Autodesk Fusion 360 part; units mm, degrees
(part 2 of 5)
sketch "roof_pa14" plane through (132.4571, 0, 0) normal (1, 0, 0) x (0, 0, -1)
  line L0 (-14.9035, -20.1869) -> (-16.1761, -17.303)
  line L1 (-16.1761, -17.303) -> (-17.2529, -14.4192)
  line L2 (-17.2529, -14.4192) -> (-18.1339, -11.5353)
  line L3 (-18.1339, -11.5353) -> (-18.8192, -8.6515)
  line L4 (-18.8192, -8.6515) -> (-19.3086, -5.7677)
  line L5 (-19.3086, -5.7677) -> (-19.6023, -2.8838)
  line L6 (-19.6023, -2.8838) -> (-19.7002, 0)
  line L7 (-19.7002, 0) -> (-19.6023, 2.8838)
  line L8 (-19.6023, 2.8838) -> (-19.3086, 5.7677)
  line L9 (-19.3086, 5.7677) -> (-18.8192, 8.6515)
  line L10 (-18.8192, 8.6515) -> (-18.1339, 11.5353)
  line L11 (-18.1339, 11.5353) -> (-17.2529, 14.4192)
  line L12 (-17.2529, 14.4192) -> (-16.1761, 17.303)
  line L13 (-16.1761, 17.303) -> (-14.9035, 20.1869)
  line L14 (-14.9035, 20.1869) -> (-12.9035, 20.1869)
  line L15 (-12.9035, 20.1869) -> (-14.1761, 17.303)
  line L16 (-14.1761, 17.303) -> (-15.2529, 14.4192)
  line L17 (-15.2529, 14.4192) -> (-16.1339, 11.5353)
  line L18 (-16.1339, 11.5353) -> (-16.8192, 8.6515)
  line L19 (-16.8192, 8.6515) -> (-17.3086, 5.7677)
  line L20 (-17.3086, 5.7677) -> (-17.6023, 2.8838)
  line L21 (-17.6023, 2.8838) -> (-17.7002, 0)
  line L22 (-17.7002, 0) -> (-17.6023, -2.8838)
  line L23 (-17.6023, -2.8838) -> (-17.3086, -5.7677)
  line L24 (-17.3086, -5.7677) -> (-16.8192, -8.6515)
  line L25 (-16.8192, -8.6515) -> (-16.1339, -11.5353)
  line L26 (-16.1339, -11.5353) -> (-15.2529, -14.4192)
  line L27 (-15.2529, -14.4192) -> (-14.1761, -17.303)
  line L28 (-14.1761, -17.303) -> (-12.9035, -20.1869)
  line L29 (-12.9035, -20.1869) -> (-14.9035, -20.1869)
ref_plane "WorkPlane30" through (137.5429, 0, 0) normal (1, 0, 0) x (0, 1, 0)
sketch "roof_pb14" plane through (137.5429, 0, 0) normal (1, 0, 0) x (0, 0, -1)
  line L0 (-13.3531, -18.2995) -> (-14.5006, -15.6853)
  line L1 (-14.5006, -15.6853) -> (-15.4714, -13.0711)
  line L2 (-15.4714, -13.0711) -> (-16.2658, -10.4568)
  line L3 (-16.2658, -10.4568) -> (-16.8836, -7.8426)
  line L4 (-16.8836, -7.8426) -> (-17.325, -5.2284)
  line L5 (-17.325, -5.2284) -> (-17.5897, -2.6142)
  line L6 (-17.5897, -2.6142) -> (-17.678, 0)
  line L7 (-17.678, 0) -> (-17.5897, 2.6142)
  line L8 (-17.5897, 2.6142) -> (-17.325, 5.2284)
  line L9 (-17.325, 5.2284) -> (-16.8836, 7.8426)
  line L10 (-16.8836, 7.8426) -> (-16.2658, 10.4568)
  line L11 (-16.2658, 10.4568) -> (-15.4714, 13.0711)
  line L12 (-15.4714, 13.0711) -> (-14.5006, 15.6853)
  line L13 (-14.5006, 15.6853) -> (-13.3531, 18.2995)
  line L14 (-13.3531, 18.2995) -> (-11.3531, 18.2995)
  line L15 (-11.3531, 18.2995) -> (-12.5006, 15.6853)
  line L16 (-12.5006, 15.6853) -> (-13.4714, 13.0711)
  line L17 (-13.4714, 13.0711) -> (-14.2658, 10.4568)
  line L18 (-14.2658, 10.4568) -> (-14.8836, 7.8426)
  line L19 (-14.8836, 7.8426) -> (-15.325, 5.2284)
  line L20 (-15.325, 5.2284) -> (-15.5897, 2.6142)
  line L21 (-15.5897, 2.6142) -> (-15.678, 0)
  line L22 (-15.678, 0) -> (-15.5897, -2.6142)
  line L23 (-15.5897, -2.6142) -> (-15.325, -5.2284)
  line L24 (-15.325, -5.2284) -> (-14.8836, -7.8426)
  line L25 (-14.8836, -7.8426) -> (-14.2658, -10.4568)
  line L26 (-14.2658, -10.4568) -> (-13.4714, -13.0711)
  line L27 (-13.4714, -13.0711) -> (-12.5006, -15.6853)
  line L28 (-12.5006, -15.6853) -> (-11.3531, -18.2995)
  line L29 (-11.3531, -18.2995) -> (-13.3531, -18.2995)
loft "Loft15" add profiles "roof_pa14", "roof_pb14" section 1 section 2 separate body makes body 15
ref_plane "WorkPlane31" through (136.7429, 0, 0) normal (1, 0, 0) x (0, 1, 0)
sketch "roof_pa15" plane through (136.7429, 0, 0) normal (1, 0, 0) x (0, 0, -1)
  line L0 (-13.3531, -18.2995) -> (-14.5006, -15.6853)
  line L1 (-14.5006, -15.6853) -> (-15.4714, -13.0711)
  line L2 (-15.4714, -13.0711) -> (-16.2658, -10.4568)
  line L3 (-16.2658, -10.4568) -> (-16.8836, -7.8426)
  line L4 (-16.8836, -7.8426) -> (-17.325, -5.2284)
  line L5 (-17.325, -5.2284) -> (-17.5897, -2.6142)
  line L6 (-17.5897, -2.6142) -> (-17.678, 0)
  line L7 (-17.678, 0) -> (-17.5897, 2.6142)
  line L8 (-17.5897, 2.6142) -> (-17.325, 5.2284)
  line L9 (-17.325, 5.2284) -> (-16.8836, 7.8426)
  line L10 (-16.8836, 7.8426) -> (-16.2658, 10.4568)
  line L11 (-16.2658, 10.4568) -> (-15.4714, 13.0711)
  line L12 (-15.4714, 13.0711) -> (-14.5006, 15.6853)
  line L13 (-14.5006, 15.6853) -> (-13.3531, 18.2995)
  line L14 (-13.3531, 18.2995) -> (-11.3531, 18.2995)
  line L15 (-11.3531, 18.2995) -> (-12.5006, 15.6853)
  line L16 (-12.5006, 15.6853) -> (-13.4714, 13.0711)
  line L17 (-13.4714, 13.0711) -> (-14.2658, 10.4568)
  line L18 (-14.2658, 10.4568) -> (-14.8836, 7.8426)
  line L19 (-14.8836, 7.8426) -> (-15.325, 5.2284)
  line L20 (-15.325, 5.2284) -> (-15.5897, 2.6142)
  line L21 (-15.5897, 2.6142) -> (-15.678, 0)
  line L22 (-15.678, 0) -> (-15.5897, -2.6142)
  line L23 (-15.5897, -2.6142) -> (-15.325, -5.2284)
  line L24 (-15.325, -5.2284) -> (-14.8836, -7.8426)
  line L25 (-14.8836, -7.8426) -> (-14.2658, -10.4568)
  line L26 (-14.2658, -10.4568) -> (-13.4714, -13.0711)
  line L27 (-13.4714, -13.0711) -> (-12.5006, -15.6853)
  line L28 (-12.5006, -15.6853) -> (-11.3531, -18.2995)
  line L29 (-11.3531, -18.2995) -> (-13.3531, -18.2995)
ref_plane "WorkPlane32" through (141.8286, 0, 0) normal (1, 0, 0) x (0, 1, 0)
sketch "roof_pb15" plane through (141.8286, 0, 0) normal (1, 0, 0) x (0, 0, -1)
  line L0 (-11.8605, -16.4823) -> (-12.8874, -14.1277)
  line L1 (-12.8874, -14.1277) -> (-13.7563, -11.7731)
  line L2 (-13.7563, -11.7731) -> (-14.4672, -9.4185)
  line L3 (-14.4672, -9.4185) -> (-15.0202, -7.0639)
  line L4 (-15.0202, -7.0639) -> (-15.4151, -4.7092)
  line L5 (-15.4151, -4.7092) -> (-15.6521, -2.3546)
  line L6 (-15.6521, -2.3546) -> (-15.7311, 0)
  line L7 (-15.7311, 0) -> (-15.6521, 2.3546)
  line L8 (-15.6521, 2.3546) -> (-15.4151, 4.7092)
  line L9 (-15.4151, 4.7092) -> (-15.0202, 7.0639)
  line L10 (-15.0202, 7.0639) -> (-14.4672, 9.4185)
  line L11 (-14.4672, 9.4185) -> (-13.7563, 11.7731)
  line L12 (-13.7563, 11.7731) -> (-12.8874, 14.1277)
  line L13 (-12.8874, 14.1277) -> (-11.8605, 16.4823)
  line L14 (-11.8605, 16.4823) -> (-9.8605, 16.4823)
  line L15 (-9.8605, 16.4823) -> (-10.8874, 14.1277)
  line L16 (-10.8874, 14.1277) -> (-11.7563, 11.7731)
  line L17 (-11.7563, 11.7731) -> (-12.4672, 9.4185)
  line L18 (-12.4672, 9.4185) -> (-13.0202, 7.0639)
  line L19 (-13.0202, 7.0639) -> (-13.4151, 4.7092)
  line L20 (-13.4151, 4.7092) -> (-13.6521, 2.3546)
  line L21 (-13.6521, 2.3546) -> (-13.7311, 0)
  line L22 (-13.7311, 0) -> (-13.6521, -2.3546)
  line L23 (-13.6521, -2.3546) -> (-13.4151, -4.7092)
  line L24 (-13.4151, -4.7092) -> (-13.0202, -7.0639)
  line L25 (-13.0202, -7.0639) -> (-12.4672, -9.4185)
  line L26 (-12.4672, -9.4185) -> (-11.7563, -11.7731)
  line L27 (-11.7563, -11.7731) -> (-10.8874, -14.1277)
  line L28 (-10.8874, -14.1277) -> (-9.8605, -16.4823)
  line L29 (-9.8605, -16.4823) -> (-11.8605, -16.4823)
loft "Loft16" add profiles "roof_pa15", "roof_pb15" section 1 section 2 separate body makes body 16
ref_plane "WorkPlane33" through (141.0286, 0, 0) normal (1, 0, 0) x (0, 1, 0)
sketch "roof_pa16" plane through (141.0286, 0, 0) normal (1, 0, 0) x (0, 0, -1)
  line L0 (-11.8605, -16.4823) -> (-12.8874, -14.1277)
  line L1 (-12.8874, -14.1277) -> (-13.7563, -11.7731)
  line L2 (-13.7563, -11.7731) -> (-14.4672, -9.4185)
  line L3 (-14.4672, -9.4185) -> (-15.0202, -7.0639)
  line L4 (-15.0202, -7.0639) -> (-15.4151, -4.7092)
  line L5 (-15.4151, -4.7092) -> (-15.6521, -2.3546)
  line L6 (-15.6521, -2.3546) -> (-15.7311, 0)
  line L7 (-15.7311, 0) -> (-15.6521, 2.3546)
  line L8 (-15.6521, 2.3546) -> (-15.4151, 4.7092)
  line L9 (-15.4151, 4.7092) -> (-15.0202, 7.0639)
  line L10 (-15.0202, 7.0639) -> (-14.4672, 9.4185)
  line L11 (-14.4672, 9.4185) -> (-13.7563, 11.7731)
  line L12 (-13.7563, 11.7731) -> (-12.8874, 14.1277)
  line L13 (-12.8874, 14.1277) -> (-11.8605, 16.4823)
  line L14 (-11.8605, 16.4823) -> (-9.8605, 16.4823)
  line L15 (-9.8605, 16.4823) -> (-10.8874, 14.1277)
  line L16 (-10.8874, 14.1277) -> (-11.7563, 11.7731)
  line L17 (-11.7563, 11.7731) -> (-12.4672, 9.4185)
  line L18 (-12.4672, 9.4185) -> (-13.0202, 7.0639)
  line L19 (-13.0202, 7.0639) -> (-13.4151, 4.7092)
  line L20 (-13.4151, 4.7092) -> (-13.6521, 2.3546)
  line L21 (-13.6521, 2.3546) -> (-13.7311, 0)
  line L22 (-13.7311, 0) -> (-13.6521, -2.3546)
  line L23 (-13.6521, -2.3546) -> (-13.4151, -4.7092)
  line L24 (-13.4151, -4.7092) -> (-13.0202, -7.0639)
  line L25 (-13.0202, -7.0639) -> (-12.4672, -9.4185)
  line L26 (-12.4672, -9.4185) -> (-11.7563, -11.7731)
  line L27 (-11.7563, -11.7731) -> (-10.8874, -14.1277)
  line L28 (-10.8874, -14.1277) -> (-9.8605, -16.4823)
  line L29 (-9.8605, -16.4823) -> (-11.8605, -16.4823)
ref_plane "WorkPlane34" through (146.1143, 0, 0) normal (1, 0, 0) x (0, 1, 0)
sketch "roof_pb16" plane through (146.1143, 0, 0) normal (1, 0, 0) x (0, 0, -1)
  line L0 (-10.4123, -14.7193) -> (-11.3222, -12.6165)
  line L1 (-11.3222, -12.6165) -> (-12.0922, -10.5138)
  line L2 (-12.0922, -10.5138) -> (-12.7222, -8.411)
  line L3 (-12.7222, -8.411) -> (-13.2121, -6.3083)
  line L4 (-13.2121, -6.3083) -> (-13.5621, -4.2055)
  line L5 (-13.5621, -4.2055) -> (-13.7721, -2.1028)
  line L6 (-13.7721, -2.1028) -> (-13.8421, 0)
  line L7 (-13.8421, 0) -> (-13.7721, 2.1028)
  line L8 (-13.7721, 2.1028) -> (-13.5621, 4.2055)
  line L9 (-13.5621, 4.2055) -> (-13.2121, 6.3083)
  line L10 (-13.2121, 6.3083) -> (-12.7222, 8.411)
  line L11 (-12.7222, 8.411) -> (-12.0922, 10.5138)
  line L12 (-12.0922, 10.5138) -> (-11.3222, 12.6165)
  line L13 (-11.3222, 12.6165) -> (-10.4123, 14.7193)
  line L14 (-10.4123, 14.7193) -> (-8.4123, 14.7193)
  line L15 (-8.4123, 14.7193) -> (-9.3222, 12.6165)
  line L16 (-9.3222, 12.6165) -> (-10.0922, 10.5138)
  line L17 (-10.0922, 10.5138) -> (-10.7222, 8.411)
  line L18 (-10.7222, 8.411) -> (-11.2121, 6.3083)
  line L19 (-11.2121, 6.3083) -> (-11.5621, 4.2055)
  line L20 (-11.5621, 4.2055) -> (-11.7721, 2.1028)
  line L21 (-11.7721, 2.1028) -> (-11.8421, 0)
  line L22 (-11.8421, 0) -> (-11.7721, -2.1028)
  line L23 (-11.7721, -2.1028) -> (-11.5621, -4.2055)
  line L24 (-11.5621, -4.2055) -> (-11.2121, -6.3083)
  line L25 (-11.2121, -6.3083) -> (-10.7222, -8.411)
  line L26 (-10.7222, -8.411) -> (-10.0922, -10.5138)
  line L27 (-10.0922, -10.5138) -> (-9.3222, -12.6165)
  line L28 (-9.3222, -12.6165) -> (-8.4123, -14.7193)
  line L29 (-8.4123, -14.7193) -> (-10.4123, -14.7193)
loft "Loft17" add profiles "roof_pa16", "roof_pb16" section 1 section 2 separate body makes body 17
ref_plane "WorkPlane35" through (145.3143, 0, 0) normal (1, 0, 0) x (0, 1, 0)
sketch "roof_pa17" plane through (145.3143, 0, 0) normal (1, 0, 0) x (0, 0, -1)
  line L0 (-10.4123, -14.7193) -> (-11.3222, -12.6165)
  line L1 (-11.3222, -12.6165) -> (-12.0922, -10.5138)
  line L2 (-12.0922, -10.5138) -> (-12.7222, -8.411)
  line L3 (-12.7222, -8.411) -> (-13.2121, -6.3083)
  line L4 (-13.2121, -6.3083) -> (-13.5621, -4.2055)
  line L5 (-13.5621, -4.2055) -> (-13.7721, -2.1028)
  line L6 (-13.7721, -2.1028) -> (-13.8421, 0)
  line L7 (-13.8421, 0) -> (-13.7721, 2.1028)
  line L8 (-13.7721, 2.1028) -> (-13.5621, 4.2055)
  line L9 (-13.5621, 4.2055) -> (-13.2121, 6.3083)
  line L10 (-13.2121, 6.3083) -> (-12.7222, 8.411)
  line L11 (-12.7222, 8.411) -> (-12.0922, 10.5138)
  line L12 (-12.0922, 10.5138) -> (-11.3222, 12.6165)
  line L13 (-11.3222, 12.6165) -> (-10.4123, 14.7193)
  line L14 (-10.4123, 14.7193) -> (-8.4123, 14.7193)
  line L15 (-8.4123, 14.7193) -> (-9.3222, 12.6165)
  line L16 (-9.3222, 12.6165) -> (-10.0922, 10.5138)
  line L17 (-10.0922, 10.5138) -> (-10.7222, 8.411)
  line L18 (-10.7222, 8.411) -> (-11.2121, 6.3083)
  line L19 (-11.2121, 6.3083) -> (-11.5621, 4.2055)
  line L20 (-11.5621, 4.2055) -> (-11.7721, 2.1028)
  line L21 (-11.7721, 2.1028) -> (-11.8421, 0)
  line L22 (-11.8421, 0) -> (-11.7721, -2.1028)
  line L23 (-11.7721, -2.1028) -> (-11.5621, -4.2055)
  line L24 (-11.5621, -4.2055) -> (-11.2121, -6.3083)
  line L25 (-11.2121, -6.3083) -> (-10.7222, -8.411)
  line L26 (-10.7222, -8.411) -> (-10.0922, -10.5138)
  line L27 (-10.0922, -10.5138) -> (-9.3222, -12.6165)
  line L28 (-9.3222, -12.6165) -> (-8.4123, -14.7193)
  line L29 (-8.4123, -14.7193) -> (-10.4123, -14.7193)
ref_plane "WorkPlane36" through (150, 0, 0) normal (1, 0, 0) x (0, 1, 0)
sketch "roof_pb17" plane through (150, 0, 0) normal (1, 0, 0) x (0, 0, -1)
  line L0 (-9, -13) -> (-9.7959, -11.1429)
  line L1 (-9.7959, -11.1429) -> (-10.4694, -9.2857)
  line L2 (-10.4694, -9.2857) -> (-11.0204, -7.4286)
  line L3 (-11.0204, -7.4286) -> (-11.449, -5.5714)
  line L4 (-11.449, -5.5714) -> (-11.7551, -3.7143)
  line L5 (-11.7551, -3.7143) -> (-11.9388, -1.8571)
  line L6 (-11.9388, -1.8571) -> (-12, 0)
  line L7 (-12, 0) -> (-11.9388, 1.8571)
  line L8 (-11.9388, 1.8571) -> (-11.7551, 3.7143)
  line L9 (-11.7551, 3.7143) -> (-11.449, 5.5714)
  line L10 (-11.449, 5.5714) -> (-11.0204, 7.4286)
  line L11 (-11.0204, 7.4286) -> (-10.4694, 9.2857)
  line L12 (-10.4694, 9.2857) -> (-9.7959, 11.1429)
  line L13 (-9.7959, 11.1429) -> (-9, 13)
  line L14 (-9, 13) -> (-7, 13)
  line L15 (-7, 13) -> (-7.7959, 11.1429)
  line L16 (-7.7959, 11.1429) -> (-8.4694, 9.2857)
  line L17 (-8.4694, 9.2857) -> (-9.0204, 7.4286)
  line L18 (-9.0204, 7.4286) -> (-9.449, 5.5714)
  line L19 (-9.449, 5.5714) -> (-9.7551, 3.7143)
  line L20 (-9.7551, 3.7143) -> (-9.9388, 1.8571)
  line L21 (-9.9388, 1.8571) -> (-10, 0)
  line L22 (-10, 0) -> (-9.9388, -1.8571)
  line L23 (-9.9388, -1.8571) -> (-9.7551, -3.7143)
  line L24 (-9.7551, -3.7143) -> (-9.449, -5.5714)
  line L25 (-9.449, -5.5714) -> (-9.0204, -7.4286)
  line L26 (-9.0204, -7.4286) -> (-8.4694, -9.2857)
  line L27 (-8.4694, -9.2857) -> (-7.7959, -11.1429)
  line L28 (-7.7959, -11.1429) -> (-7, -13)
  line L29 (-7, -13) -> (-9, -13)
loft "Loft18" add profiles "roof_pa17", "roof_pb17" section 1 section 2 separate body makes body 18
ref_plane "WorkPlane37" through (-24, 0, 0) normal (1, 0, 0) x (0, 1, 0)
sketch "belly_pa00" plane through (-24, 0, 0) normal (1, 0, 0) x (0, 0, -1)
  line L0 (24.5, -33) -> (25.6939, -28.2857)
  line L1 (25.6939, -28.2857) -> (26.7041, -23.5714)
  line L2 (26.7041, -23.5714) -> (27.5306, -18.8571)
  line L3 (27.5306, -18.8571) -> (28.1735, -14.1429)
  line L4 (28.1735, -14.1429) -> (28.6327, -9.4286)
  line L5 (28.6327, -9.4286) -> (28.9082, -4.7143)
  line L6 (28.9082, -4.7143) -> (29, 0)
  line L7 (29, 0) -> (28.9082, 4.7143)
  line L8 (28.9082, 4.7143) -> (28.6327, 9.4286)
  line L9 (28.6327, 9.4286) -> (28.1735, 14.1429)
  line L10 (28.1735, 14.1429) -> (27.5306, 18.8571)
  line L11 (27.5306, 18.8571) -> (26.7041, 23.5714)
  line L12 (26.7041, 23.5714) -> (25.6939, 28.2857)
  line L13 (25.6939, 28.2857) -> (24.5, 33)
  line L14 (24.5, 33) -> (22.5, 33)
  line L15 (22.5, 33) -> (23.6939, 28.2857)
  line L16 (23.6939, 28.2857) -> (24.7041, 23.5714)
  line L17 (24.7041, 23.5714) -> (25.5306, 18.8571)
  line L18 (25.5306, 18.8571) -> (26.1735, 14.1429)
  line L19 (26.1735, 14.1429) -> (26.6327, 9.4286)
  line L20 (26.6327, 9.4286) -> (26.9082, 4.7143)
  line L21 (26.9082, 4.7143) -> (27, 0)
  line L22 (27, 0) -> (26.9082, -4.7143)
  line L23 (26.9082, -4.7143) -> (26.6327, -9.4286)
  line L24 (26.6327, -9.4286) -> (26.1735, -14.1429)
  line L25 (26.1735, -14.1429) -> (25.5306, -18.8571)
  line L26 (25.5306, -18.8571) -> (24.7041, -23.5714)
  line L27 (24.7041, -23.5714) -> (23.6939, -28.2857)
  line L28 (23.6939, -28.2857) -> (22.5, -33)
  line L29 (22.5, -33) -> (24.5, -33)
ref_plane "WorkPlane38" through (-20.1714, 0, 0) normal (1, 0, 0) x (0, 1, 0)
sketch "belly_pb00" plane through (-20.1714, 0, 0) normal (1, 0, 0) x (0, 0, -1)
  line L0 (24.3997, -32.8496) -> (25.6069, -28.1568)
  line L1 (25.6069, -28.1568) -> (26.6284, -23.464)
  line L2 (26.6284, -23.464) -> (27.4641, -18.7712)
  line L3 (27.4641, -18.7712) -> (28.1141, -14.0784)
  line L4 (28.1141, -14.0784) -> (28.5784, -9.3856)
  line L5 (28.5784, -9.3856) -> (28.857, -4.6928)
  line L6 (28.857, -4.6928) -> (28.9499, 0)
  line L7 (28.9499, 0) -> (28.857, 4.6928)
  line L8 (28.857, 4.6928) -> (28.5784, 9.3856)
  line L9 (28.5784, 9.3856) -> (28.1141, 14.0784)
  line L10 (28.1141, 14.0784) -> (27.4641, 18.7712)
  line L11 (27.4641, 18.7712) -> (26.6284, 23.464)
  line L12 (26.6284, 23.464) -> (25.6069, 28.1568)
  line L13 (25.6069, 28.1568) -> (24.3997, 32.8496)
  line L14 (24.3997, 32.8496) -> (22.3997, 32.8496)
  line L15 (22.3997, 32.8496) -> (23.6069, 28.1568)
  line L16 (23.6069, 28.1568) -> (24.6284, 23.464)
  line L17 (24.6284, 23.464) -> (25.4641, 18.7712)
  line L18 (25.4641, 18.7712) -> (26.1141, 14.0784)
  line L19 (26.1141, 14.0784) -> (26.5784, 9.3856)
  line L20 (26.5784, 9.3856) -> (26.857, 4.6928)
  line L21 (26.857, 4.6928) -> (26.9499, 0)
  line L22 (26.9499, 0) -> (26.857, -4.6928)
  line L23 (26.857, -4.6928) -> (26.5784, -9.3856)
  line L24 (26.5784, -9.3856) -> (26.1141, -14.0784)
  line L25 (26.1141, -14.0784) -> (25.4641, -18.7712)
  line L26 (25.4641, -18.7712) -> (24.6284, -23.464)
  line L27 (24.6284, -23.464) -> (23.6069, -28.1568)
  line L28 (23.6069, -28.1568) -> (22.3997, -32.8496)
  line L29 (22.3997, -32.8496) -> (24.3997, -32.8496)
loft "Loft19" add profiles "belly_pa00", "belly_pb00" section 1 section 2 separate body makes body 19
ref_plane "WorkPlane39" through (-20.9714, 0, 0) normal (1, 0, 0) x (0, 1, 0)
sketch "belly_pa01" plane through (-20.9714, 0, 0) normal (1, 0, 0) x (0, 0, -1)
  line L0 (24.3997, -32.8496) -> (25.6069, -28.1568)
  line L1 (25.6069, -28.1568) -> (26.6284, -23.464)
  line L2 (26.6284, -23.464) -> (27.4641, -18.7712)
  line L3 (27.4641, -18.7712) -> (28.1141, -14.0784)
  line L4 (28.1141, -14.0784) -> (28.5784, -9.3856)
  line L5 (28.5784, -9.3856) -> (28.857, -4.6928)
  line L6 (28.857, -4.6928) -> (28.9499, 0)
  line L7 (28.9499, 0) -> (28.857, 4.6928)
  line L8 (28.857, 4.6928) -> (28.5784, 9.3856)
  line L9 (28.5784, 9.3856) -> (28.1141, 14.0784)
  line L10 (28.1141, 14.0784) -> (27.4641, 18.7712)
  line L11 (27.4641, 18.7712) -> (26.6284, 23.464)
  line L12 (26.6284, 23.464) -> (25.6069, 28.1568)
  line L13 (25.6069, 28.1568) -> (24.3997, 32.8496)
  line L14 (24.3997, 32.8496) -> (22.3997, 32.8496)
  line L15 (22.3997, 32.8496) -> (23.6069, 28.1568)
  line L16 (23.6069, 28.1568) -> (24.6284, 23.464)
  line L17 (24.6284, 23.464) -> (25.4641, 18.7712)
  line L18 (25.4641, 18.7712) -> (26.1141, 14.0784)
  line L19 (26.1141, 14.0784) -> (26.5784, 9.3856)
  line L20 (26.5784, 9.3856) -> (26.857, 4.6928)
  line L21 (26.857, 4.6928) -> (26.9499, 0)
  line L22 (26.9499, 0) -> (26.857, -4.6928)
  line L23 (26.857, -4.6928) -> (26.5784, -9.3856)
  line L24 (26.5784, -9.3856) -> (26.1141, -14.0784)
  line L25 (26.1141, -14.0784) -> (25.4641, -18.7712)
  line L26 (25.4641, -18.7712) -> (24.6284, -23.464)
  line L27 (24.6284, -23.464) -> (23.6069, -28.1568)
  line L28 (23.6069, -28.1568) -> (22.3997, -32.8496)
  line L29 (22.3997, -32.8496) -> (24.3997, -32.8496)
ref_plane "WorkPlane40" through (-16.7429, 0, 0) normal (1, 0, 0) x (0, 1, 0)
sketch "belly_pb01" plane through (-16.7429, 0, 0) normal (1, 0, 0) x (0, 0, -1)
  line L0 (24.1039, -32.4058) -> (25.3503, -27.7764)
  line L1 (25.3503, -27.7764) -> (26.405, -23.147)
  line L2 (26.405, -23.147) -> (27.2679, -18.5176)
  line L3 (27.2679, -18.5176) -> (27.939, -13.8882)
  line L4 (27.939, -13.8882) -> (28.4184, -9.2588)
  line L5 (28.4184, -9.2588) -> (28.7061, -4.6294)
  line L6 (28.7061, -4.6294) -> (28.8019, 0)
  line L7 (28.8019, 0) -> (28.7061, 4.6294)
  line L8 (28.7061, 4.6294) -> (28.4184, 9.2588)
  line L9 (28.4184, 9.2588) -> (27.939, 13.8882)
  line L10 (27.939, 13.8882) -> (27.2679, 18.5176)
  line L11 (27.2679, 18.5176) -> (26.405, 23.147)
  line L12 (26.405, 23.147) -> (25.3503, 27.7764)
  line L13 (25.3503, 27.7764) -> (24.1039, 32.4058)
  line L14 (24.1039, 32.4058) -> (22.1039, 32.4058)
  line L15 (22.1039, 32.4058) -> (23.3503, 27.7764)
  line L16 (23.3503, 27.7764) -> (24.405, 23.147)
  line L17 (24.405, 23.147) -> (25.2679, 18.5176)
  line L18 (25.2679, 18.5176) -> (25.939, 13.8882)
  line L19 (25.939, 13.8882) -> (26.4184, 9.2588)
  line L20 (26.4184, 9.2588) -> (26.7061, 4.6294)
  line L21 (26.7061, 4.6294) -> (26.8019, 0)
  line L22 (26.8019, 0) -> (26.7061, -4.6294)
  line L23 (26.7061, -4.6294) -> (26.4184, -9.2588)
  line L24 (26.4184, -9.2588) -> (25.939, -13.8882)
  line L25 (25.939, -13.8882) -> (25.2679, -18.5176)
  line L26 (25.2679, -18.5176) -> (24.405, -23.147)
  line L27 (24.405, -23.147) -> (23.3503, -27.7764)
  line L28 (23.3503, -27.7764) -> (22.1039, -32.4058)
  line L29 (22.1039, -32.4058) -> (24.1039, -32.4058)
loft "Loft20" add profiles "belly_pa01", "belly_pb01" section 1 section 2 separate body makes body 20
ref_plane "WorkPlane41" through (-17.5429, 0, 0) normal (1, 0, 0) x (0, 1, 0)
sketch "belly_pa02" plane through (-17.5429, 0, 0) normal (1, 0, 0) x (0, 0, -1)
  line L0 (24.1039, -32.4058) -> (25.3503, -27.7764)
  line L1 (25.3503, -27.7764) -> (26.405, -23.147)
  line L2 (26.405, -23.147) -> (27.2679, -18.5176)
  line L3 (27.2679, -18.5176) -> (27.939, -13.8882)
  line L4 (27.939, -13.8882) -> (28.4184, -9.2588)
  line L5 (28.4184, -9.2588) -> (28.7061, -4.6294)
  line L6 (28.7061, -4.6294) -> (28.8019, 0)
  line L7 (28.8019, 0) -> (28.7061, 4.6294)
  line L8 (28.7061, 4.6294) -> (28.4184, 9.2588)
  line L9 (28.4184, 9.2588) -> (27.939, 13.8882)
  line L10 (27.939, 13.8882) -> (27.2679, 18.5176)
  line L11 (27.2679, 18.5176) -> (26.405, 23.147)
  line L12 (26.405, 23.147) -> (25.3503, 27.7764)
  line L13 (25.3503, 27.7764) -> (24.1039, 32.4058)
  line L14 (24.1039, 32.4058) -> (22.1039, 32.4058)
  line L15 (22.1039, 32.4058) -> (23.3503, 27.7764)
  line L16 (23.3503, 27.7764) -> (24.405, 23.147)
  line L17 (24.405, 23.147) -> (25.2679, 18.5176)
  line L18 (25.2679, 18.5176) -> (25.939, 13.8882)
  line L19 (25.939, 13.8882) -> (26.4184, 9.2588)
  line L20 (26.4184, 9.2588) -> (26.7061, 4.6294)
  line L21 (26.7061, 4.6294) -> (26.8019, 0)
  line L22 (26.8019, 0) -> (26.7061, -4.6294)
  line L23 (26.7061, -4.6294) -> (26.4184, -9.2588)
  line L24 (26.4184, -9.2588) -> (25.939, -13.8882)
  line L25 (25.939, -13.8882) -> (25.2679, -18.5176)
  line L26 (25.2679, -18.5176) -> (24.405, -23.147)
  line L27 (24.405, -23.147) -> (23.3503, -27.7764)
  line L28 (23.3503, -27.7764) -> (22.1039, -32.4058)
  line L29 (22.1039, -32.4058) -> (24.1039, -32.4058)
ref_plane "WorkPlane42" through (-13.3143, 0, 0) normal (1, 0, 0) x (0, 1, 0)
sketch "belly_pb02" plane through (-13.3143, 0, 0) normal (1, 0, 0) x (0, 0, -1)
  line L0 (23.6273, -31.691) -> (24.937, -27.1637)
  line L1 (24.937, -27.1637) -> (26.0451, -22.6364)
  line L2 (26.0451, -22.6364) -> (26.9518, -18.1091)
  line L3 (26.9518, -18.1091) -> (27.657, -13.5819)
  line L4 (27.657, -13.5819) -> (28.1607, -9.0546)
  line L5 (28.1607, -9.0546) -> (28.4629, -4.5273)
  line L6 (28.4629, -4.5273) -> (28.5637, 0)
  line L7 (28.5637, 0) -> (28.4629, 4.5273)
  line L8 (28.4629, 4.5273) -> (28.1607, 9.0546)
  line L9 (28.1607, 9.0546) -> (27.657, 13.5819)
  line L10 (27.657, 13.5819) -> (26.9518, 18.1091)
  line L11 (26.9518, 18.1091) -> (26.0451, 22.6364)
  line L12 (26.0451, 22.6364) -> (24.937, 27.1637)
  line L13 (24.937, 27.1637) -> (23.6273, 31.691)
  line L14 (23.6273, 31.691) -> (21.6273, 31.691)
  line L15 (21.6273, 31.691) -> (22.937, 27.1637)
  line L16 (22.937, 27.1637) -> (24.0451, 22.6364)
  line L17 (24.0451, 22.6364) -> (24.9518, 18.1091)
  line L18 (24.9518, 18.1091) -> (25.657, 13.5819)
  line L19 (25.657, 13.5819) -> (26.1607, 9.0546)
  line L20 (26.1607, 9.0546) -> (26.4629, 4.5273)
  line L21 (26.4629, 4.5273) -> (26.5637, 0)
  line L22 (26.5637, 0) -> (26.4629, -4.5273)
  line L23 (26.4629, -4.5273) -> (26.1607, -9.0546)
  line L24 (26.1607, -9.0546) -> (25.657, -13.5819)
  line L25 (25.657, -13.5819) -> (24.9518, -18.1091)
  line L26 (24.9518, -18.1091) -> (24.0451, -22.6364)
  line L27 (24.0451, -22.6364) -> (22.937, -27.1637)
  line L28 (22.937, -27.1637) -> (21.6273, -31.691)
  line L29 (21.6273, -31.691) -> (23.6273, -31.691)
loft "Loft21" add profiles "belly_pa02", "belly_pb02" section 1 section 2 separate body makes body 21
ref_plane "WorkPlane43" through (-14.1143, 0, 0) normal (1, 0, 0) x (0, 1, 0)
sketch "belly_pa03" plane through (-14.1143, 0, 0) normal (1, 0, 0) x (0, 0, -1)
  line L0 (23.6273, -31.691) -> (24.937, -27.1637)
  line L1 (24.937, -27.1637) -> (26.0451, -22.6364)
  line L2 (26.0451, -22.6364) -> (26.9518, -18.1091)
  line L3 (26.9518, -18.1091) -> (27.657, -13.5819)
  line L4 (27.657, -13.5819) -> (28.1607, -9.0546)
  line L5 (28.1607, -9.0546) -> (28.4629, -4.5273)
  line L6 (28.4629, -4.5273) -> (28.5637, 0)
  line L7 (28.5637, 0) -> (28.4629, 4.5273)
  line L8 (28.4629, 4.5273) -> (28.1607, 9.0546)
  line L9 (28.1607, 9.0546) -> (27.657, 13.5819)
  line L10 (27.657, 13.5819) -> (26.9518, 18.1091)
  line L11 (26.9518, 18.1091) -> (26.0451, 22.6364)
  line L12 (26.0451, 22.6364) -> (24.937, 27.1637)
  line L13 (24.937, 27.1637) -> (23.6273, 31.691)
  line L14 (23.6273, 31.691) -> (21.6273, 31.691)
  line L15 (21.6273, 31.691) -> (22.937, 27.1637)
  line L16 (22.937, 27.1637) -> (24.0451, 22.6364)
  line L17 (24.0451, 22.6364) -> (24.9518, 18.1091)
  line L18 (24.9518, 18.1091) -> (25.657, 13.5819)
  line L19 (25.657, 13.5819) -> (26.1607, 9.0546)
  line L20 (26.1607, 9.0546) -> (26.4629, 4.5273)
  line L21 (26.4629, 4.5273) -> (26.5637, 0)
  line L22 (26.5637, 0) -> (26.4629, -4.5273)
  line L23 (26.4629, -4.5273) -> (26.1607, -9.0546)
  line L24 (26.1607, -9.0546) -> (25.657, -13.5819)
  line L25 (25.657, -13.5819) -> (24.9518, -18.1091)
  line L26 (24.9518, -18.1091) -> (24.0451, -22.6364)
  line L27 (24.0451, -22.6364) -> (22.937, -27.1637)
  line L28 (22.937, -27.1637) -> (21.6273, -31.691)
  line L29 (21.6273, -31.691) -> (23.6273, -31.691)
ref_plane "WorkPlane44" through (-9.8857, 0, 0) normal (1, 0, 0) x (0, 1, 0)
sketch "belly_pb03" plane through (-9.8857, 0, 0) normal (1, 0, 0) x (0, 0, -1)
  line L0 (22.994, -30.7409) -> (24.3876, -26.3494)
  line L1 (24.3876, -26.3494) -> (25.5669, -21.9578)
  line L2 (25.5669, -21.9578) -> (26.5317, -17.5663)
  line L3 (26.5317, -17.5663) -> (27.2821, -13.1747)
  line L4 (27.2821, -13.1747) -> (27.8182, -8.7831)
  line L5 (27.8182, -8.7831) -> (28.1398, -4.3916)
  line L6 (28.1398, -4.3916) -> (28.247, 0)
  line L7 (28.247, 0) -> (28.1398, 4.3916)
  line L8 (28.1398, 4.3916) -> (27.8182, 8.7831)
  line L9 (27.8182, 8.7831) -> (27.2821, 13.1747)
  line L10 (27.2821, 13.1747) -> (26.5317, 17.5663)
  line L11 (26.5317, 17.5663) -> (25.5669, 21.9578)
  line L12 (25.5669, 21.9578) -> (24.3876, 26.3494)
  line L13 (24.3876, 26.3494) -> (22.994, 30.7409)
  line L14 (22.994, 30.7409) -> (20.994, 30.7409)
  line L15 (20.994, 30.7409) -> (22.3876, 26.3494)
  line L16 (22.3876, 26.3494) -> (23.5669, 21.9578)
  line L17 (23.5669, 21.9578) -> (24.5317, 17.5663)
  line L18 (24.5317, 17.5663) -> (25.2821, 13.1747)
  line L19 (25.2821, 13.1747) -> (25.8182, 8.7831)
  line L20 (25.8182, 8.7831) -> (26.1398, 4.3916)
  line L21 (26.1398, 4.3916) -> (26.247, 0)
  line L22 (26.247, 0) -> (26.1398, -4.3916)
  line L23 (26.1398, -4.3916) -> (25.8182, -8.7831)
  line L24 (25.8182, -8.7831) -> (25.2821, -13.1747)
  line L25 (25.2821, -13.1747) -> (24.5317, -17.5663)
  line L26 (24.5317, -17.5663) -> (23.5669, -21.9578)
  line L27 (23.5669, -21.9578) -> (22.3876, -26.3494)
  line L28 (22.3876, -26.3494) -> (20.994, -30.7409)
  line L29 (20.994, -30.7409) -> (22.994, -30.7409)
loft "Loft22" add profiles "belly_pa03", "belly_pb03" section 1 section 2 separate body makes body 22
ref_plane "WorkPlane45" through (-10.6857, 0, 0) normal (1, 0, 0) x (0, 1, 0)
sketch "belly_pa04" plane through (-10.6857, 0, 0) normal (1, 0, 0) x (0, 0, -1)
  line L0 (22.994, -30.7409) -> (24.3876, -26.3494)
  line L1 (24.3876, -26.3494) -> (25.5669, -21.9578)
  line L2 (25.5669, -21.9578) -> (26.5317, -17.5663)
  line L3 (26.5317, -17.5663) -> (27.2821, -13.1747)
  line L4 (27.2821, -13.1747) -> (27.8182, -8.7831)
  line L5 (27.8182, -8.7831) -> (28.1398, -4.3916)
  line L6 (28.1398, -4.3916) -> (28.247, 0)
  line L7 (28.247, 0) -> (28.1398, 4.3916)
  line L8 (28.1398, 4.3916) -> (27.8182, 8.7831)
  line L9 (27.8182, 8.7831) -> (27.2821, 13.1747)
  line L10 (27.2821, 13.1747) -> (26.5317, 17.5663)
  line L11 (26.5317, 17.5663) -> (25.5669, 21.9578)
  line L12 (25.5669, 21.9578) -> (24.3876, 26.3494)
  line L13 (24.3876, 26.3494) -> (22.994, 30.7409)
  line L14 (22.994, 30.7409) -> (20.994, 30.7409)
  line L15 (20.994, 30.7409) -> (22.3876, 26.3494)
  line L16 (22.3876, 26.3494) -> (23.5669, 21.9578)
  line L17 (23.5669, 21.9578) -> (24.5317, 17.5663)
  line L18 (24.5317, 17.5663) -> (25.2821, 13.1747)
  line L19 (25.2821, 13.1747) -> (25.8182, 8.7831)
  line L20 (25.8182, 8.7831) -> (26.1398, 4.3916)
  line L21 (26.1398, 4.3916) -> (26.247, 0)
  line L22 (26.247, 0) -> (26.1398, -4.3916)
  line L23 (26.1398, -4.3916) -> (25.8182, -8.7831)
  line L24 (25.8182, -8.7831) -> (25.2821, -13.1747)
  line L25 (25.2821, -13.1747) -> (24.5317, -17.5663)
  line L26 (24.5317, -17.5663) -> (23.5669, -21.9578)
  line L27 (23.5669, -21.9578) -> (22.3876, -26.3494)
  line L28 (22.3876, -26.3494) -> (20.994, -30.7409)
  line L29 (20.994, -30.7409) -> (22.994, -30.7409)
ref_plane "WorkPlane46" through (-6.4571, 0, 0) normal (1, 0, 0) x (0, 1, 0)
sketch "belly_pb04" plane through (-6.4571, 0, 0) normal (1, 0, 0) x (0, 0, -1)
  line L0 (22.2355, -29.6033) -> (23.7298, -25.3743)
  line L1 (23.7298, -25.3743) -> (24.9942, -21.1452)
  line L2 (24.9942, -21.1452) -> (26.0287, -16.9162)
  line L3 (26.0287, -16.9162) -> (26.8333, -12.6871)
  line L4 (26.8333, -12.6871) -> (27.408, -8.4581)
  line L5 (27.408, -8.4581) -> (27.7528, -4.229)
  line L6 (27.7528, -4.229) -> (27.8678, 0)
  line L7 (27.8678, 0) -> (27.7528, 4.229)
  line L8 (27.7528, 4.229) -> (27.408, 8.4581)
  line L9 (27.408, 8.4581) -> (26.8333, 12.6871)
  line L10 (26.8333, 12.6871) -> (26.0287, 16.9162)
  line L11 (26.0287, 16.9162) -> (24.9942, 21.1452)
  line L12 (24.9942, 21.1452) -> (23.7298, 25.3743)
  line L13 (23.7298, 25.3743) -> (22.2355, 29.6033)
  line L14 (22.2355, 29.6033) -> (20.2355, 29.6033)
  line L15 (20.2355, 29.6033) -> (21.7298, 25.3743)
  line L16 (21.7298, 25.3743) -> (22.9942, 21.1452)
  line L17 (22.9942, 21.1452) -> (24.0287, 16.9162)
  line L18 (24.0287, 16.9162) -> (24.8333, 12.6871)
  line L19 (24.8333, 12.6871) -> (25.408, 8.4581)
  line L20 (25.408, 8.4581) -> (25.7528, 4.229)
  line L21 (25.7528, 4.229) -> (25.8678, 0)
  line L22 (25.8678, 0) -> (25.7528, -4.229)
  line L23 (25.7528, -4.229) -> (25.408, -8.4581)
  line L24 (25.408, -8.4581) -> (24.8333, -12.6871)
  line L25 (24.8333, -12.6871) -> (24.0287, -16.9162)
  line L26 (24.0287, -16.9162) -> (22.9942, -21.1452)
  line L27 (22.9942, -21.1452) -> (21.7298, -25.3743)
  line L28 (21.7298, -25.3743) -> (20.2355, -29.6033)
  line L29 (20.2355, -29.6033) -> (22.2355, -29.6033)
loft "Loft23" add profiles "belly_pa04", "belly_pb04" section 1 section 2 separate body makes body 23
ref_plane "WorkPlane47" through (-7.2571, 0, 0) normal (1, 0, 0) x (0, 1, 0)
sketch "belly_pa05" plane through (-7.2571, 0, 0) normal (1, 0, 0) x (0, 0, -1)
  line L0 (22.2355, -29.6033) -> (23.7298, -25.3743)
  line L1 (23.7298, -25.3743) -> (24.9942, -21.1452)
  line L2 (24.9942, -21.1452) -> (26.0287, -16.9162)
  line L3 (26.0287, -16.9162) -> (26.8333, -12.6871)
  line L4 (26.8333, -12.6871) -> (27.408, -8.4581)
  line L5 (27.408, -8.4581) -> (27.7528, -4.229)
  line L6 (27.7528, -4.229) -> (27.8678, 0)
  line L7 (27.8678, 0) -> (27.7528, 4.229)
  line L8 (27.7528, 4.229) -> (27.408, 8.4581)
  line L9 (27.408, 8.4581) -> (26.8333, 12.6871)
  line L10 (26.8333, 12.6871) -> (26.0287, 16.9162)
  line L11 (26.0287, 16.9162) -> (24.9942, 21.1452)
  line L12 (24.9942, 21.1452) -> (23.7298, 25.3743)
  line L13 (23.7298, 25.3743) -> (22.2355, 29.6033)
  line L14 (22.2355, 29.6033) -> (20.2355, 29.6033)
  line L15 (20.2355, 29.6033) -> (21.7298, 25.3743)
  line L16 (21.7298, 25.3743) -> (22.9942, 21.1452)
  line L17 (22.9942, 21.1452) -> (24.0287, 16.9162)
  line L18 (24.0287, 16.9162) -> (24.8333, 12.6871)
  line L19 (24.8333, 12.6871) -> (25.408, 8.4581)
  line L20 (25.408, 8.4581) -> (25.7528, 4.229)
  line L21 (25.7528, 4.229) -> (25.8678, 0)
  line L22 (25.8678, 0) -> (25.7528, -4.229)
  line L23 (25.7528, -4.229) -> (25.408, -8.4581)
  line L24 (25.408, -8.4581) -> (24.8333, -12.6871)
  line L25 (24.8333, -12.6871) -> (24.0287, -16.9162)
  line L26 (24.0287, -16.9162) -> (22.9942, -21.1452)
  line L27 (22.9942, -21.1452) -> (21.7298, -25.3743)
  line L28 (21.7298, -25.3743) -> (20.2355, -29.6033)
  line L29 (20.2355, -29.6033) -> (22.2355, -29.6033)
ref_plane "WorkPlane48" through (-3.0286, 0, 0) normal (1, 0, 0) x (0, 1, 0)
sketch "belly_pb05" plane through (-3.0286, 0, 0) normal (1, 0, 0) x (0, 0, -1)
  line L0 (21.3901, -28.3351) -> (22.9965, -24.2873)
  line L1 (22.9965, -24.2873) -> (24.3558, -20.2394)
  line L2 (24.3558, -20.2394) -> (25.4679, -16.1915)
  line L3 (25.4679, -16.1915) -> (26.3329, -12.1436)
  line L4 (26.3329, -12.1436) -> (26.9508, -8.0958)
  line L5 (26.9508, -8.0958) -> (27.3215, -4.0479)
  line L6 (27.3215, -4.0479) -> (27.445, 0)
  line L7 (27.445, 0) -> (27.3215, 4.0479)
  line L8 (27.3215, 4.0479) -> (26.9508, 8.0958)
  line L9 (26.9508, 8.0958) -> (26.3329, 12.1436)
  line L10 (26.3329, 12.1436) -> (25.4679, 16.1915)
  line L11 (25.4679, 16.1915) -> (24.3558, 20.2394)
  line L12 (24.3558, 20.2394) -> (22.9965, 24.2873)
  line L13 (22.9965, 24.2873) -> (21.3901, 28.3351)
  line L14 (21.3901, 28.3351) -> (19.3901, 28.3351)
  line L15 (19.3901, 28.3351) -> (20.9965, 24.2873)
  line L16 (20.9965, 24.2873) -> (22.3558, 20.2394)
  line L17 (22.3558, 20.2394) -> (23.4679, 16.1915)
  line L18 (23.4679, 16.1915) -> (24.3329, 12.1436)
  line L19 (24.3329, 12.1436) -> (24.9508, 8.0958)
  line L20 (24.9508, 8.0958) -> (25.3215, 4.0479)
  line L21 (25.3215, 4.0479) -> (25.445, 0)
  line L22 (25.445, 0) -> (25.3215, -4.0479)
  line L23 (25.3215, -4.0479) -> (24.9508, -8.0958)
  line L24 (24.9508, -8.0958) -> (24.3329, -12.1436)
  line L25 (24.3329, -12.1436) -> (23.4679, -16.1915)
  line L26 (23.4679, -16.1915) -> (22.3558, -20.2394)
  line L27 (22.3558, -20.2394) -> (20.9965, -24.2873)
  line L28 (20.9965, -24.2873) -> (19.3901, -28.3351)
  line L29 (19.3901, -28.3351) -> (21.3901, -28.3351)
loft "Loft24" add profiles "belly_pa05", "belly_pb05" section 1 section 2 separate body makes body 24
ref_plane "WorkPlane49" through (-3.8286, 0, 0) normal (1, 0, 0) x (0, 1, 0)
sketch "belly_pa06" plane through (-3.8286, 0, 0) normal (1, 0, 0) x (0, 0, -1)
  line L0 (21.3901, -28.3351) -> (22.9965, -24.2873)
  line L1 (22.9965, -24.2873) -> (24.3558, -20.2394)
  line L2 (24.3558, -20.2394) -> (25.4679, -16.1915)
  line L3 (25.4679, -16.1915) -> (26.3329, -12.1436)
  line L4 (26.3329, -12.1436) -> (26.9508, -8.0958)
  line L5 (26.9508, -8.0958) -> (27.3215, -4.0479)
  line L6 (27.3215, -4.0479) -> (27.445, 0)
  line L7 (27.445, 0) -> (27.3215, 4.0479)
  line L8 (27.3215, 4.0479) -> (26.9508, 8.0958)
  line L9 (26.9508, 8.0958) -> (26.3329, 12.1436)
  line L10 (26.3329, 12.1436) -> (25.4679, 16.1915)
  line L11 (25.4679, 16.1915) -> (24.3558, 20.2394)
  line L12 (24.3558, 20.2394) -> (22.9965, 24.2873)
  line L13 (22.9965, 24.2873) -> (21.3901, 28.3351)
  line L14 (21.3901, 28.3351) -> (19.3901, 28.3351)
  line L15 (19.3901, 28.3351) -> (20.9965, 24.2873)
  line L16 (20.9965, 24.2873) -> (22.3558, 20.2394)
  line L17 (22.3558, 20.2394) -> (23.4679, 16.1915)
  line L18 (23.4679, 16.1915) -> (24.3329, 12.1436)
  line L19 (24.3329, 12.1436) -> (24.9508, 8.0958)
  line L20 (24.9508, 8.0958) -> (25.3215, 4.0479)
  line L21 (25.3215, 4.0479) -> (25.445, 0)
  line L22 (25.445, 0) -> (25.3215, -4.0479)
  line L23 (25.3215, -4.0479) -> (24.9508, -8.0958)
  line L24 (24.9508, -8.0958) -> (24.3329, -12.1436)
  line L25 (24.3329, -12.1436) -> (23.4679, -16.1915)
  line L26 (23.4679, -16.1915) -> (22.3558, -20.2394)
  line L27 (22.3558, -20.2394) -> (20.9965, -24.2873)
  line L28 (20.9965, -24.2873) -> (19.3901, -28.3351)
  line L29 (19.3901, -28.3351) -> (21.3901, -28.3351)
ref_plane "WorkPlane50" through (0.4, 0, 0) normal (1, 0, 0) x (0, 1, 0)
sketch "belly_pb06" plane through (0.4, 0, 0) normal (1, 0, 0) x (0, 0, -1)
  line L0 (20.5, -27) -> (22.2245, -23.1429)
  line L1 (22.2245, -23.1429) -> (23.6837, -19.2857)
  line L2 (23.6837, -19.2857) -> (24.8776, -15.4286)
  line L3 (24.8776, -15.4286) -> (25.8061, -11.5714)
  line L4 (25.8061, -11.5714) -> (26.4694, -7.7143)
  line L5 (26.4694, -7.7143) -> (26.8673, -3.8571)
  line L6 (26.8673, -3.8571) -> (27, 0)
  line L7 (27, 0) -> (26.8673, 3.8571)
  line L8 (26.8673, 3.8571) -> (26.4694, 7.7143)
  line L9 (26.4694, 7.7143) -> (25.8061, 11.5714)
  line L10 (25.8061, 11.5714) -> (24.8776, 15.4286)
  line L11 (24.8776, 15.4286) -> (23.6837, 19.2857)
  line L12 (23.6837, 19.2857) -> (22.2245, 23.1429)
  line L13 (22.2245, 23.1429) -> (20.5, 27)
  line L14 (20.5, 27) -> (18.5, 27)
  line L15 (18.5, 27) -> (20.2245, 23.1429)
  line L16 (20.2245, 23.1429) -> (21.6837, 19.2857)
  line L17 (21.6837, 19.2857) -> (22.8776, 15.4286)
  line L18 (22.8776, 15.4286) -> (23.8061, 11.5714)
  line L19 (23.8061, 11.5714) -> (24.4694, 7.7143)
  line L20 (24.4694, 7.7143) -> (24.8673, 3.8571)
  line L21 (24.8673, 3.8571) -> (25, 0)
  line L22 (25, 0) -> (24.8673, -3.8571)
  line L23 (24.8673, -3.8571) -> (24.4694, -7.7143)
  line L24 (24.4694, -7.7143) -> (23.8061, -11.5714)
  line L25 (23.8061, -11.5714) -> (22.8776, -15.4286)
  line L26 (22.8776, -15.4286) -> (21.6837, -19.2857)
  line L27 (21.6837, -19.2857) -> (20.2245, -23.1429)
  line L28 (20.2245, -23.1429) -> (18.5, -27)
  line L29 (18.5, -27) -> (20.5, -27)
loft "Loft25" add profiles "belly_pa06", "belly_pb06" section 1 section 2 separate body makes body 25
ref_plane "WorkPlane51" through (-0.4, 0, 0) normal (1, 0, 0) x (0, 1, 0)
sketch "belly_pa07" plane through (-0.4, 0, 0) normal (1, 0, 0) x (0, 0, -1)
  line L0 (20.5, -27) -> (22.2245, -23.1429)
  line L1 (22.2245, -23.1429) -> (23.6837, -19.2857)
  line L2 (23.6837, -19.2857) -> (24.8776, -15.4286)
  line L3 (24.8776, -15.4286) -> (25.8061, -11.5714)
  line L4 (25.8061, -11.5714) -> (26.4694, -7.7143)
  line L5 (26.4694, -7.7143) -> (26.8673, -3.8571)
  line L6 (26.8673, -3.8571) -> (27, 0)
  line L7 (27, 0) -> (26.8673, 3.8571)
  line L8 (26.8673, 3.8571) -> (26.4694, 7.7143)
  line L9 (26.4694, 7.7143) -> (25.8061, 11.5714)
  line L10 (25.8061, 11.5714) -> (24.8776, 15.4286)
  line L11 (24.8776, 15.4286) -> (23.6837, 19.2857)
  line L12 (23.6837, 19.2857) -> (22.2245, 23.1429)
  line L13 (22.2245, 23.1429) -> (20.5, 27)
  line L14 (20.5, 27) -> (18.5, 27)
  line L15 (18.5, 27) -> (20.2245, 23.1429)
  line L16 (20.2245, 23.1429) -> (21.6837, 19.2857)
  line L17 (21.6837, 19.2857) -> (22.8776, 15.4286)
  line L18 (22.8776, 15.4286) -> (23.8061, 11.5714)
  line L19 (23.8061, 11.5714) -> (24.4694, 7.7143)
  line L20 (24.4694, 7.7143) -> (24.8673, 3.8571)
  line L21 (24.8673, 3.8571) -> (25, 0)
  line L22 (25, 0) -> (24.8673, -3.8571)
  line L23 (24.8673, -3.8571) -> (24.4694, -7.7143)
  line L24 (24.4694, -7.7143) -> (23.8061, -11.5714)
  line L25 (23.8061, -11.5714) -> (22.8776, -15.4286)
  line L26 (22.8776, -15.4286) -> (21.6837, -19.2857)
  line L27 (21.6837, -19.2857) -> (20.2245, -23.1429)
  line L28 (20.2245, -23.1429) -> (18.5, -27)
  line L29 (18.5, -27) -> (20.5, -27)
ref_plane "WorkPlane52" through (30.4, 0, 0) normal (1, 0, 0) x (0, 1, 0)
sketch "belly_pb07" plane through (30.4, 0, 0) normal (1, 0, 0) x (0, 0, -1)
  line L0 (20.5, -27) -> (22.2245, -23.1429)
  line L1 (22.2245, -23.1429) -> (23.6837, -19.2857)
  line L2 (23.6837, -19.2857) -> (24.8776, -15.4286)
  line L3 (24.8776, -15.4286) -> (25.8061, -11.5714)
  line L4 (25.8061, -11.5714) -> (26.4694, -7.7143)
  line L5 (26.4694, -7.7143) -> (26.8673, -3.8571)
  line L6 (26.8673, -3.8571) -> (27, 0)
  line L7 (27, 0) -> (26.8673, 3.8571)
  line L8 (26.8673, 3.8571) -> (26.4694, 7.7143)
  line L9 (26.4694, 7.7143) -> (25.8061, 11.5714)
  line L10 (25.8061, 11.5714) -> (24.8776, 15.4286)
  line L11 (24.8776, 15.4286) -> (23.6837, 19.2857)
  line L12 (23.6837, 19.2857) -> (22.2245, 23.1429)
  line L13 (22.2245, 23.1429) -> (20.5, 27)
  line L14 (20.5, 27) -> (18.5, 27)
  line L15 (18.5, 27) -> (20.2245, 23.1429)
  line L16 (20.2245, 23.1429) -> (21.6837, 19.2857)
  line L17 (21.6837, 19.2857) -> (22.8776, 15.4286)
  line L18 (22.8776, 15.4286) -> (23.8061, 11.5714)
  line L19 (23.8061, 11.5714) -> (24.4694, 7.7143)
  line L20 (24.4694, 7.7143) -> (24.8673, 3.8571)
  line L21 (24.8673, 3.8571) -> (25, 0)
  line L22 (25, 0) -> (24.8673, -3.8571)
  line L23 (24.8673, -3.8571) -> (24.4694, -7.7143)
  line L24 (24.4694, -7.7143) -> (23.8061, -11.5714)
  line L25 (23.8061, -11.5714) -> (22.8776, -15.4286)
  line L26 (22.8776, -15.4286) -> (21.6837, -19.2857)
  line L27 (21.6837, -19.2857) -> (20.2245, -23.1429)
  line L28 (20.2245, -23.1429) -> (18.5, -27)
  line L29 (18.5, -27) -> (20.5, -27)
loft "Loft26" add profiles "belly_pa07", "belly_pb07" section 1 section 2 separate body makes body 26
ref_plane "WorkPlane53" through (29.6, 0, 0) normal (1, 0, 0) x (0, 1, 0)
sketch "belly_pa08" plane through (29.6, 0, 0) normal (1, 0, 0) x (0, 0, -1)
  line L0 (20.5, -27) -> (22.2245, -23.1429)
  line L1 (22.2245, -23.1429) -> (23.6837, -19.2857)
  line L2 (23.6837, -19.2857) -> (24.8776, -15.4286)
  line L3 (24.8776, -15.4286) -> (25.8061, -11.5714)
  line L4 (25.8061, -11.5714) -> (26.4694, -7.7143)
  line L5 (26.4694, -7.7143) -> (26.8673, -3.8571)
  line L6 (26.8673, -3.8571) -> (27, 0)
  line L7 (27, 0) -> (26.8673, 3.8571)
  line L8 (26.8673, 3.8571) -> (26.4694, 7.7143)
  line L9 (26.4694, 7.7143) -> (25.8061, 11.5714)
  line L10 (25.8061, 11.5714) -> (24.8776, 15.4286)
  line L11 (24.8776, 15.4286) -> (23.6837, 19.2857)
  line L12 (23.6837, 19.2857) -> (22.2245, 23.1429)
  line L13 (22.2245, 23.1429) -> (20.5, 27)
  line L14 (20.5, 27) -> (18.5, 27)
  line L15 (18.5, 27) -> (20.2245, 23.1429)
  line L16 (20.2245, 23.1429) -> (21.6837, 19.2857)
  line L17 (21.6837, 19.2857) -> (22.8776, 15.4286)
  line L18 (22.8776, 15.4286) -> (23.8061, 11.5714)
  line L19 (23.8061, 11.5714) -> (24.4694, 7.7143)
  line L20 (24.4694, 7.7143) -> (24.8673, 3.8571)
  line L21 (24.8673, 3.8571) -> (25, 0)
  line L22 (25, 0) -> (24.8673, -3.8571)
  line L23 (24.8673, -3.8571) -> (24.4694, -7.7143)
  line L24 (24.4694, -7.7143) -> (23.8061, -11.5714)
  line L25 (23.8061, -11.5714) -> (22.8776, -15.4286)
  line L26 (22.8776, -15.4286) -> (21.6837, -19.2857)
  line L27 (21.6837, -19.2857) -> (20.2245, -23.1429)
  line L28 (20.2245, -23.1429) -> (18.5, -27)
  line L29 (18.5, -27) -> (20.5, -27)
ref_plane "WorkPlane54" through (60.4, 0, 0) normal (1, 0, 0) x (0, 1, 0)
sketch "belly_pb08" plane through (60.4, 0, 0) normal (1, 0, 0) x (0, 0, -1)
  line L0 (20.5, -27) -> (22.2245, -23.1429)
  line L1 (22.2245, -23.1429) -> (23.6837, -19.2857)
  line L2 (23.6837, -19.2857) -> (24.8776, -15.4286)
  line L3 (24.8776, -15.4286) -> (25.8061, -11.5714)
  line L4 (25.8061, -11.5714) -> (26.4694, -7.7143)
  line L5 (26.4694, -7.7143) -> (26.8673, -3.8571)
  line L6 (26.8673, -3.8571) -> (27, 0)
  line L7 (27, 0) -> (26.8673, 3.8571)
  line L8 (26.8673, 3.8571) -> (26.4694, 7.7143)
  line L9 (26.4694, 7.7143) -> (25.8061, 11.5714)
  line L10 (25.8061, 11.5714) -> (24.8776, 15.4286)
  line L11 (24.8776, 15.4286) -> (23.6837, 19.2857)
  line L12 (23.6837, 19.2857) -> (22.2245, 23.1429)
  line L13 (22.2245, 23.1429) -> (20.5, 27)
  line L14 (20.5, 27) -> (18.5, 27)
  line L15 (18.5, 27) -> (20.2245, 23.1429)
  line L16 (20.2245, 23.1429) -> (21.6837, 19.2857)
  line L17 (21.6837, 19.2857) -> (22.8776, 15.4286)
  line L18 (22.8776, 15.4286) -> (23.8061, 11.5714)
  line L19 (23.8061, 11.5714) -> (24.4694, 7.7143)
  line L20 (24.4694, 7.7143) -> (24.8673, 3.8571)
  line L21 (24.8673, 3.8571) -> (25, 0)
  line L22 (25, 0) -> (24.8673, -3.8571)
  line L23 (24.8673, -3.8571) -> (24.4694, -7.7143)
  line L24 (24.4694, -7.7143) -> (23.8061, -11.5714)
  line L25 (23.8061, -11.5714) -> (22.8776, -15.4286)
  line L26 (22.8776, -15.4286) -> (21.6837, -19.2857)
  line L27 (21.6837, -19.2857) -> (20.2245, -23.1429)
  line L28 (20.2245, -23.1429) -> (18.5, -27)
  line L29 (18.5, -27) -> (20.5, -27)
loft "Loft27" add profiles "belly_pa08", "belly_pb08" section 1 section 2 separate body makes body 27
ref_plane "WorkPlane55" through (59.6, 0, 0) normal (1, 0, 0) x (0, 1, 0)
sketch "belly_pa09" plane through (59.6, 0, 0) normal (1, 0, 0) x (0, 0, -1)
  line L0 (20.5, -27) -> (22.2245, -23.1429)
  line L1 (22.2245, -23.1429) -> (23.6837, -19.2857)
  line L2 (23.6837, -19.2857) -> (24.8776, -15.4286)
  line L3 (24.8776, -15.4286) -> (25.8061, -11.5714)
  line L4 (25.8061, -11.5714) -> (26.4694, -7.7143)
  line L5 (26.4694, -7.7143) -> (26.8673, -3.8571)
  line L6 (26.8673, -3.8571) -> (27, 0)
  line L7 (27, 0) -> (26.8673, 3.8571)
  line L8 (26.8673, 3.8571) -> (26.4694, 7.7143)
  line L9 (26.4694, 7.7143) -> (25.8061, 11.5714)
  line L10 (25.8061, 11.5714) -> (24.8776, 15.4286)
  line L11 (24.8776, 15.4286) -> (23.6837, 19.2857)
  line L12 (23.6837, 19.2857) -> (22.2245, 23.1429)
  line L13 (22.2245, 23.1429) -> (20.5, 27)
  line L14 (20.5, 27) -> (18.5, 27)
  line L15 (18.5, 27) -> (20.2245, 23.1429)
  line L16 (20.2245, 23.1429) -> (21.6837, 19.2857)
  line L17 (21.6837, 19.2857) -> (22.8776, 15.4286)
  line L18 (22.8776, 15.4286) -> (23.8061, 11.5714)
  line L19 (23.8061, 11.5714) -> (24.4694, 7.7143)
  line L20 (24.4694, 7.7143) -> (24.8673, 3.8571)
  line L21 (24.8673, 3.8571) -> (25, 0)
  line L22 (25, 0) -> (24.8673, -3.8571)
  line L23 (24.8673, -3.8571) -> (24.4694, -7.7143)
  line L24 (24.4694, -7.7143) -> (23.8061, -11.5714)
  line L25 (23.8061, -11.5714) -> (22.8776, -15.4286)
  line L26 (22.8776, -15.4286) -> (21.6837, -19.2857)
  line L27 (21.6837, -19.2857) -> (20.2245, -23.1429)
  line L28 (20.2245, -23.1429) -> (18.5, -27)
  line L29 (18.5, -27) -> (20.5, -27)
ref_plane "WorkPlane56" through (90.4, 0, 0) normal (1, 0, 0) x (0, 1, 0)
sketch "belly_pb09" plane through (90.4, 0, 0) normal (1, 0, 0) x (0, 0, -1)
  line L0 (20.5, -27) -> (22.2245, -23.1429)
  line L1 (22.2245, -23.1429) -> (23.6837, -19.2857)
  line L2 (23.6837, -19.2857) -> (24.8776, -15.4286)
  line L3 (24.8776, -15.4286) -> (25.8061, -11.5714)
  line L4 (25.8061, -11.5714) -> (26.4694, -7.7143)
  line L5 (26.4694, -7.7143) -> (26.8673, -3.8571)
  line L6 (26.8673, -3.8571) -> (27, 0)
  line L7 (27, 0) -> (26.8673, 3.8571)
  line L8 (26.8673, 3.8571) -> (26.4694, 7.7143)
  line L9 (26.4694, 7.7143) -> (25.8061, 11.5714)
  line L10 (25.8061, 11.5714) -> (24.8776, 15.4286)
  line L11 (24.8776, 15.4286) -> (23.6837, 19.2857)
  line L12 (23.6837, 19.2857) -> (22.2245, 23.1429)
  line L13 (22.2245, 23.1429) -> (20.5, 27)
  line L14 (20.5, 27) -> (18.5, 27)
  line L15 (18.5, 27) -> (20.2245, 23.1429)
  line L16 (20.2245, 23.1429) -> (21.6837, 19.2857)
  line L17 (21.6837, 19.2857) -> (22.8776, 15.4286)
  line L18 (22.8776, 15.4286) -> (23.8061, 11.5714)
  line L19 (23.8061, 11.5714) -> (24.4694, 7.7143)
  line L20 (24.4694, 7.7143) -> (24.8673, 3.8571)
  line L21 (24.8673, 3.8571) -> (25, 0)
  line L22 (25, 0) -> (24.8673, -3.8571)
  line L23 (24.8673, -3.8571) -> (24.4694, -7.7143)
  line L24 (24.4694, -7.7143) -> (23.8061, -11.5714)
  line L25 (23.8061, -11.5714) -> (22.8776, -15.4286)
  line L26 (22.8776, -15.4286) -> (21.6837, -19.2857)
  line L27 (21.6837, -19.2857) -> (20.2245, -23.1429)
  line L28 (20.2245, -23.1429) -> (18.5, -27)
  line L29 (18.5, -27) -> (20.5, -27)
loft "Loft28" add profiles "belly_pa09", "belly_pb09" section 1 section 2 separate body makes body 28
ref_plane "WorkPlane57" through (89.6, 0, 0) normal (1, 0, 0) x (0, 1, 0)
sketch "belly_pa10" plane through (89.6, 0, 0) normal (1, 0, 0) x (0, 0, -1)
  line L0 (20.5, -27) -> (22.2245, -23.1429)
  line L1 (22.2245, -23.1429) -> (23.6837, -19.2857)
  line L2 (23.6837, -19.2857) -> (24.8776, -15.4286)
  line L3 (24.8776, -15.4286) -> (25.8061, -11.5714)
  line L4 (25.8061, -11.5714) -> (26.4694, -7.7143)
  line L5 (26.4694, -7.7143) -> (26.8673, -3.8571)
  line L6 (26.8673, -3.8571) -> (27, 0)
  line L7 (27, 0) -> (26.8673, 3.8571)
  line L8 (26.8673, 3.8571) -> (26.4694, 7.7143)
  line L9 (26.4694, 7.7143) -> (25.8061, 11.5714)
  line L10 (25.8061, 11.5714) -> (24.8776, 15.4286)
  line L11 (24.8776, 15.4286) -> (23.6837, 19.2857)
  line L12 (23.6837, 19.2857) -> (22.2245, 23.1429)
  line L13 (22.2245, 23.1429) -> (20.5, 27)
  line L14 (20.5, 27) -> (18.5, 27)
  line L15 (18.5, 27) -> (20.2245, 23.1429)
  line L16 (20.2245, 23.1429) -> (21.6837, 19.2857)
  line L17 (21.6837, 19.2857) -> (22.8776, 15.4286)
  line L18 (22.8776, 15.4286) -> (23.8061, 11.5714)
  line L19 (23.8061, 11.5714) -> (24.4694, 7.7143)
  line L20 (24.4694, 7.7143) -> (24.8673, 3.8571)
  line L21 (24.8673, 3.8571) -> (25, 0)
  line L22 (25, 0) -> (24.8673, -3.8571)
  line L23 (24.8673, -3.8571) -> (24.4694, -7.7143)
  line L24 (24.4694, -7.7143) -> (23.8061, -11.5714)
  line L25 (23.8061, -11.5714) -> (22.8776, -15.4286)
  line L26 (22.8776, -15.4286) -> (21.6837, -19.2857)
  line L27 (21.6837, -19.2857) -> (20.2245, -23.1429)
  line L28 (20.2245, -23.1429) -> (18.5, -27)
  line L29 (18.5, -27) -> (20.5, -27)
ref_plane "WorkPlane58" through (120.4, 0, 0) normal (1, 0, 0) x (0, 1, 0)